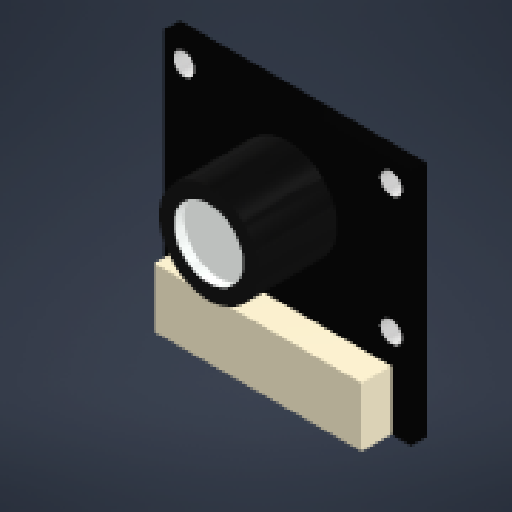
# Autodesk Inventor part: camera
Saved by Autodesk Inventor 2026.2 (Build 302298010, 298A)
## iProperties
Created: 2026-07-16
Part Number: camera
Material: Generic
Document SubType Name: Modeling
Designer: User
Density: 1 g/cm^3
Appearance: Default
Author: User
Autodesk Inventor part; units mm, degrees
ref_plane "YZ Plane" through (0, 0, 0) normal (1, 0, 0) x (0, 1, 0)
ref_plane "XZ Plane" through (0, 0, 0) normal (0, 1, 0) x (-1, 0, 0)
ref_plane "XY Plane" through (0, 0, 0) normal (0, 0, 1) x (1, 0, 0)
sketch "Sketch1" plane through (0, 0, 0) normal (0, 0, 1) x (1, 0, 0)
  line L0 (0, 0) -> (25, 0)
  line L1 (25, 0) -> (25, 24)
  line L2 (25, 24) -> (0, 24)
  line L3 (0, 24) -> (0, 0)
  dimension "d0" = 25
  dimension "d1" = 24
  constraints: 8 end point, 2 parallel, 1 horizontal, 1 perpendicular
  measures "d0" distance of L2.end L1.end
  measures "d1" distance of L1.end L0.end
extrude "Extrusion1" add sketch "Sketch1" along normal blind 1.6
sketch "Sketch2" plane through (0, 0, 1.6) normal (0, 0, 1) x (1, 0, 0)
  line L0 (2, 22) -> (2, 24)
  line L1 (25, 24) -> (0, 24) projected
  line L2 (23, 22) -> (25, 22)
  line L3 (25, 0) -> (25, 24) projected
  line L4 (23, 22) -> (23, 24)
  line L5 (23, 9) -> (25, 9)
  line L6 (2, 9) -> (2, 0)
  line L7 (0, 0) -> (25, 0) projected
  line L8 (2, 22) -> (0, 22)
  line L9 (0, 24) -> (0, 0) projected
  line L10 (23, 9) -> (23, 0)
  line L11 (2, 9) -> (0, 9)
  dimension "d6" = 2
  dimension "d8" = 9
  dimension "d9" = 2
  dimension "d11" = 2
  dimension "d12" = 2
  dimension "d13" = 2
  dimension "d14" = 9
  dimension "d15" = 2
  constraints: 16 end point, 8 point on line, 4 perpendicular, 2 horizontal, 2 vertical
  measures "d6" distance of L0.start L0.end
  measures "d8" distance of L6.start L6.end
  measures "d9" distance of L5.start L5.end
  measures "d11" distance of L2.start L2.end
  measures "d12" distance of L2.start L4.end
  measures "d13" distance of L0.start L8.end
  measures "d14" distance of L5.start L10.end
  measures "d15" distance of L6.start L11.end
hole "Hole1" at (2, 22, 1.6) at (23, 22, 1.6) at (23, 9, 1.6) at (2, 9, 1.6) direction (0, 0, -1) diameter 2.2 end through all
sketch "Sketch3" plane through (0, 0, 1.6) normal (0, 0, 1) x (1, 0, 0)
  line L0 (25, 24) -> (0, 24) projected
  line L1 (0, 24) -> (0, 0) projected
  line L2 (0, 0) -> (25, 0) projected
  line L3 (2, 6) -> (23, 6)
  line L4 (23, 6) -> (23, 0)
  line L5 (23, 0) -> (2, 0)
  line L6 (2, 0) -> (2, 6)
  line L7 (2, 6) -> (23, 0) construction
  line L8 (23, 6) -> (2, 0) construction
  point P0 (12.5, 3)
  dimension "d29" = 21
  constraints: 12 end point, 2 midpoint, 2 parallel, 1 horizontal, 1 perpendicular, 1 point on line
  measures "d29" distance of L4.end L5.end
extrude "Extrusion2" add sketch "Sketch3" along normal blind 3
sketch "Sketch4" plane through (0, 0, 1.6) normal (0, 0, 1) x (1, 0, 0)
  line L0 (25, 24) -> (0, 24) projected
  line L1 (2, 6) -> (23, 6) projected
  circle A0 centre (2, 22) radius 1.1 projected
  circle A1 centre (2, 9) radius 1.1 projected
  circle A2 centre (12.5, 15.5) radius 5
  point P0 (0, 0)
  dimension "d30" = 10
  constraints: 1 centre point
  measures "d30" diameter of A2
extrude "Extrusion3" add sketch "Sketch4" along normal blind 8 contours A2
sketch "Sketch5" plane through (12.5, 15.5, 9.6) normal (0, 0, 1) x (1, 0, 0)
  circle A0 centre (0, 0) radius 3.5
  point P0 (-12.5, -15.5)
  dimension "d33" = 7
  constraints: 1 centre point
  measures "d33" diameter of A0
extrude "Extrusion4" cut sketch "Sketch5" against normal blind 1
body "Solid1"
